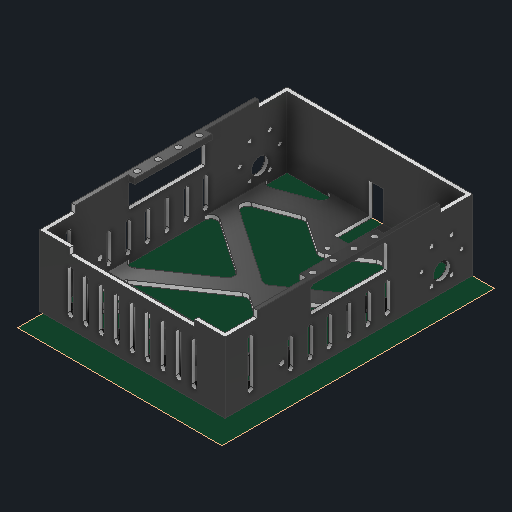
# Autodesk Inventor part: 01_4_2_support_electronique_moteur_v2
Saved by Autodesk Inventor 2026 (Build 300175000, 175)
## iProperties
Created: 2025-06-04
Part Number: 01_4_2_support_electronique_moteur_v2
Material: Générique
Document SubType Name: Modeling
Designer: virgi
Density: 1 g/cm^3
Appearance: Par défaut
Author: virgi
Autodesk Inventor part; units mm, degrees
ref_plane "YZ Plane" through (0, 0, 0) normal (1, 0, 0) x (0, 1, 0)
ref_plane "XZ Plane" through (0, 0, 0) normal (0, 1, 0) x (-1, 0, 0)
ref_plane "XY Plane" through (0, 0, 0) normal (0, 0, 1) x (1, 0, 0)
sketch "Esquisse1" plane through (0, 0, 0) normal (0, 1, 0) x (-1, 0, 0)
  line L0 (-72, -96) -> (72, -96)
  line L1 (72, -96) -> (72, 96)
  line L2 (72, 96) -> (-72, 96)
  line L3 (-72, 96) -> (-72, -96)
  line L4 (-72, -96) -> (72, 96) construction
  line L5 (72, -96) -> (-72, 96) construction
  point P0 (0, 0)
  dimension "d0" = 192
  dimension "d1" = 144
  constraints: 12 end point, 2 midpoint, 2 parallel, 1 horizontal, 1 perpendicular
  measures "d0" distance of L0.end L1.end
  measures "d1" distance of L0.start L0.end
extrude "bloc initial" add sketch "Esquisse1" along normal blind 60
sketch "Esquisse2" plane through (0, 60, 0) normal (0, 1, 0) x (1, 0, 0)
  line L0 (69, 93) -> (-69, 93)
  line L1 (-69, 93) -> (-69, -93)
  line L2 (-69, -93) -> (69, -93)
  line L3 (69, -93) -> (69, 93)
  line L4 (69, 93) -> (-69, -93) construction
  line L5 (-69, 93) -> (69, -93) construction
  line L6 (-72, -96) -> (72, -96) projected
  line L7 (-72, 96) -> (-72, -96) projected
  point P0 (0, 0)
  dimension "d4" = 3
  dimension "d5" = 3
  constraints: 12 end point, 2 midpoint, 2 parallel, 1 horizontal, 1 perpendicular
  measures "d4" distance between parallel lines of L6 L2
  measures "d5" distance between parallel lines of L7 L1
extrude "volume interieur" cut sketch "Esquisse2" against normal blind 57
sketch "Esquisse3" plane through (0, 60, 0) normal (0, 1, 0) x (1, 0, 0)
  line L0 (-69, 30) -> (-64, 30)
  line L1 (-64, 30) -> (-64, -30)
  line L2 (-64, -30) -> (-69, -30)
  line L3 (-69, -30) -> (-69, 30)
  line L4 (-69, 30) -> (-64, -30) construction
  line L5 (-64, 30) -> (-69, -30) construction
  line L6 (-69, -93) -> (-69, 93) projected
  line L7 (-72, 96) -> (-72, -96) projected
  point P0 (0, 0)
  point P1 (-66.5, 0)
  point P2 (-72, -30)
  point P3 (-72, 30)
  dimension "d13" = 60
  dimension "d14" = 0
  dimension "d148" = 5
  constraints: 12 end point, 2 midpoint, 2 parallel, 1 collinear, 1 horizontal, 1 perpendicular
  measures "d13" distance between parallel lines of L0 L2
  measures "d14" vertical distance of point (0, 0) point (-66.5, 0)
  measures "d148" distance between parallel lines of L6 L1
extrude "vorsprung de maintient" add sketch "Esquisse3" against normal blind 4
sketch "Esquisse4" plane through (0, 60, 0) normal (0, 1, 0) x (1, 0, 0)
  line L0 (-64, -30) -> (-64, 30) projected
  line L1 (-69, 30) -> (-69, 93) projected
  line L2 (-72, 96) -> (-72, -96) projected
  point P0 (0, 0)
  point P1 (-72, 30)
  point P2 (-68, 24)
  point P3 (-105.6247, 24)
  dimension "d153" = 4
  constraints: 1 horizontal alignment, 2 other
  measures "d153" distance from line of L2 point (-68, 24)
hole "8*trous attache chassis" at (-68, 60, -24) direction (0, -1, 0) diameter 4.5 depth 20 tip angle 118
pattern_linear "Réseau rectangulaire1" count 4 spacing 16 along (0, 0, 1) of "8*trous attache chassis"
mirror "Mise en miroir2" about plane through (0, 0, 0) normal (1, 0, 0) of "vorsprung de maintient", "8*trous attache chassis", "Réseau rectangulaire1"
sketch "Esquisse5" plane through (0, 60, 0) normal (0, 1, 0) x (1, 0, 0)
  line L0 (-72, 71) -> (72, 71)
  line L1 (72, 71) -> (72, 96)
  line L2 (72, 96) -> (-72, 96)
  line L3 (-72, 96) -> (-72, 71)
  line L4 (-72, 71) -> (72, 96) construction
  line L5 (72, 71) -> (-72, 96) construction
  point P0 (0, 0)
  point P1 (0, 83.5)
  dimension "d29" = 71
  dimension "d32" = 0
  constraints: 12 end point, 2 coincident, 2 midpoint, 2 parallel, 1 horizontal, 1 perpendicular
  measures "d29" distance from line of point (0, 0) L0
  measures "d32" horizontal distance of point (0, 0) point (0, 83.5)
extrude "encoches chassis" cut sketch "Esquisse5" against normal blind 5.5
mirror "Mise en miroir encoches" about plane through (0, 0, 0) normal (0, 0, 1) of "encoches chassis"
sketch "Esquisse7" plane through (-72, 0, -96) normal (-1, 0, 0) x (0, 0, 1)
  line L0 (192, 0) -> (192, 60) projected
  line L1 (0, 0) -> (192, 0) projected
  line L2 (25, 60) -> (192, 60) projected
  point P0 (96, 0)
  point P1 (148, 15)
  point P2 (192, 54.5)
  point P3 (126, 60)
  point P4 (167, 60)
  dimension "d47" = 44
  dimension "d49" = 45
  measures "d47" distance from line of L0 point (148, 15)
  measures "d49" distance from line of L2 point (148, 15)
hole "axe roues arrieres" at (-72, 15, 52) direction (1, 0, 0) diameter 4.5 end through all
sketch "Esquisse8" plane through (-72, 0, -96) normal (-1, 0, 0) x (0, 0, 1)
  line L0 (0, 60) -> (192, 60) projected
  line L1 (0, 0) -> (0, 60) projected
  line L2 (0, 0) -> (192, 0) projected
  point P0 (96, 0)
  point P1 (24, 15)
  point P2 (25, 60)
  point P3 (66, 60)
  point P4 (0, 54.5)
  point P5 (96, 0)
  dimension "d57" = 45
  dimension "d60" = 72
  constraints: 1 midpoint
  measures "d57" distance from line of point (24, 15) L0
  measures "d60" horizontal distance of point (24, 15) point (96, 0)
hole "axes moteur" at (-72, 15, -72) direction (1, 0, 0) diameter 13.2 end through all
sketch "Esquisse9" plane through (-72, 0, -96) normal (-1, 0, 0) x (0, 0, 1)
  circle A0 centre (24, 22) radius 15.5 construction
  circle A1 centre (24, 15) radius 6.6 construction
  point P0 (96, 0)
  point P1 (39.5, 22)
  point P2 (31.75, 35.4234)
  point P3 (16.25, 35.4234)
  point P4 (8.5, 22)
  point P5 (16.25, 8.5766)
  point P6 (31.75, 8.5766)
  dimension "d70" = 31
  dimension "d68" = 7
  dimension "d69" = 0
  dimension "d71" = 0
  dimension "d74" = 360
  constraints: 2 coincident, 1 horizontal alignment, 13 other
  measures "d68" distance of A1.centre point (24, 22)
  measures "d69" horizontal distance of A1.centre point (24, 22)
  measures "d71" vertical distance of point (24, 22) point (39.5, 22)
hole "trous moteur" at (-72, 22, -56.5) at (-72, 35.4234, -64.25) at (-72, 35.4234, -79.75) at (-72, 22, -87.5) at (-72, 8.5766, -79.75) at (-72, 8.5766, -64.25) direction (1, 0, 0) diameter 3.5 end through all
sketch "Esquisse12" plane through (0, 60, 0) normal (0, 1, 0) x (1, 0, 0)
  line L0 (-48.25, -96) -> (48.25, -96)
  line L1 (48.25, -96) -> (48.25, -93)
  line L2 (48.25, -93) -> (-48.25, -93)
  line L3 (-48.25, -93) -> (-48.25, -96)
  line L4 (-48.25, -96) -> (48.25, -93) construction
  line L5 (48.25, -96) -> (-48.25, -93) construction
  line L6 (72, -96) -> (-72, -96) projected
  line L7 (-69, -93) -> (69, -93) projected
  point P0 (0, 0)
  point P1 (0, -94.5)
  point P2 (65, -96)
  point P3 (-65, -96)
  point P4 (-65, -92)
  point P5 (65, -92)
  dimension "d106" = 96.5
  dimension "d109" = 0
  constraints: 12 end point, 2 horizontal, 2 midpoint, 2 parallel, 1 collinear, 1 perpendicular, 1 other
  measures "d106" distance between parallel lines of L3 L1
  measures "d109" horizontal distance of point (0, 0) point (0, -94.5)
extrude "encoche chassis arriere" cut sketch "Esquisse12" against normal blind 10.5
sketch "Esquisse13" plane through (0, 3, 0) normal (0, 1, 0) x (1, 0, 0)
  line L0 (0, 5.631) -> (-69, 53)
  line L1 (69, 53) -> (0, 5.631)
  line L2 (0, -116.7872) -> (0, 160.5594) construction
  line L3 (-69, -93) -> (-69, 93) projected
  line L4 (-77.1225, 0) -> (59.0886, 0) construction
  line L5 (-74.2887, 0) -> (57.0105, 0) construction
  line L6 (0, -5.631) -> (-69, -53)
  line L7 (-69, -53) -> (69, -53)
  line L8 (69, -53) -> (0, -5.631)
  line L9 (-13, 0) -> (-69, -38.4444)
  line L10 (-69, -38.4444) -> (-69, 38.4444)
  line L11 (-13, 0) -> (-69, 38.4444)
  line L12 (-69, -38.4444) -> (-69, 38.4444)
  line L13 (13, 0) -> (69, -38.4444)
  line L14 (69, -38.4444) -> (69, 38.4444)
  line L15 (13, 0) -> (69, 38.4444)
  line L16 (-69, 53) -> (-29, 67.8231)
  line L17 (9.4839, 93) -> (69, 70.9446)
  line L18 (69, 70.9446) -> (69, 93)
  line L19 (69, 93) -> (9.4839, 93)
  line L20 (69, 93) -> (69, -93) projected
  line L21 (69, 93) -> (-69, 93) projected
  line L22 (-9.4839, 93) -> (-69, 70.9446)
  line L23 (-69, 70.9446) -> (-69, 93)
  line L24 (-69, 93) -> (-9.4839, 93)
  line L25 (-48.25, -93) -> (48.25, -93) projected
  line L26 (-72, 96) -> (72, 96) projected
  line L27 (8.125, 96) -> (8.125, 65.9) construction
  line L28 (8.125, 96) -> (38.225, 96) construction
  line L29 (8.125, 65.9) -> (0, 65.9) construction
  line L30 (8.125, 96) -> (0, 96) construction
  line L31 (-8.125, 96) -> (-8.125, 65.9) construction
  line L32 (-8.125, 65.9) -> (0, 65.9) construction
  line L33 (-8.125, 96) -> (0, 96) construction
  circle A0 centre (-1.5, 54.9) radius 2 construction
  line L34 (-29, 67.8231) -> (0, 48.2272)
  line L35 (29, 67.8231) -> (0, 48.2272)
  line L36 (29, 67.8231) -> (69, 53)
  point P0 (0, 0)
  point P1 (-69, -71)
  point P2 (-69, 71)
  point P3 (0, 83.6463)
  point P4 (69, 71)
  point P5 (69, -71)
  point P6 (-69, 70.9446)
  point P7 (-69, 70.9446)
  point P8 (65, 92)
  point P9 (-65, 92)
  point P10 (-65, 96)
  point P11 (65, 96)
  dimension "d114" = 12
  dimension "d126" = 40
  dimension "d136" = 30.1
  dimension "d137" = 90
  dimension "d138" = 8.125
  dimension "d139" = 4
  dimension "d142" = 11
  dimension "d143" = 9.625
  dimension "d144" = 35
  dimension "d161" = 56
  constraints: 60 end point, 13 point on line, 13 symmetric about line, 4 vertical, 3 parallel, 2 horizontal, 2 perpendicular, 1 centre point, 1 collinear, 1 midpoint, 10 other
  measures "d114" distance from line of L11 L0.start
  measures "d126" distance between parallel lines of L25 L7
  measures "d136" distance of L27.start L27.end
  measures "d137" angle of L27 L28
  measures "d138" distance of L27.end L29.end
  measures "d139" diameter of A0
  measures "d142" distance from line of L29 A0.centre
  measures "d143" distance from line of L27 A0.centre
  measures "d144" distance of L16.end L34.end
  measures "d161" distance from line of L3 L9.start
extrude "structure bas" cut sketch "Esquisse13" against normal blind 10 contours L0 L16 L34 L35 L36 L1 | L11 L9 L3 | L3 L21 L22 | L17 L19 L18 | L14 L13 L15 | L6 L8 L7
sketch "Esquisse14" plane through (0, 3, 0) normal (0, 1, 0) x (1, 0, 0)
  line L0 (-69, -56) -> (69, -56)
  line L1 (69, -56) -> (69, -58)
  line L2 (69, -58) -> (-69, -58)
  line L3 (-69, -58) -> (-69, -56)
  line L4 (-48.25, -93) -> (48.25, -93) projected
  line L5 (-69, -93) -> (-69, -53) projected
  line L6 (69, -53) -> (69, -93) projected
  point P0 (0, 0)
  point P1 (-69, -57)
  point P2 (69, -57)
  dimension "d117" = 35
  dimension "d118" = 2
  constraints: 8 end point, 3 point on line, 2 midpoint, 2 parallel, 1 horizontal, 1 perpendicular
  measures "d117" distance between parallel lines of L4 L2
  measures "d118" distance between parallel lines of L2 L0
extrude "Extrusion8" add sketch "Esquisse14" along normal blind 10
chamfer "Chanfrein3" distance 2 angle 45 1 edges at (0, 3, 56)
fillet "Congé1" radius 5 19 edges at (69, 1.5, -53) (0, 1.5, -5.631) (0, 1.5, 5.631) (69, 1.5, 53) (69, 1.5, 38.4444) (69, 1.5, -38.4444) (-13, 1.5, 0) (-69, 1.5, -38.4444) (-69, 1.5, -53) (-9.4839, 1.5, -93) (9.4839, 1.5, -93) (69, 1.5, -70.9446) (-69, 1.5, 38.4444) (-69, 1.5, 53) (13, 1.5, 0) (29, 1.5, -67.8231) (-29, 1.5, -67.8231) (0, 1.5, -48.2272) (-69, 1.5, -70.9446)
sketch "Esquisse15" plane through (0, 0, 0) normal (0, -1, 0) x (1, 0, 0)
  line L0 (72, -96) -> (-72, -96) projected
  line L1 (5.625, -96) -> (5.625, -65.9)
  line L2 (5.625, -96) -> (35.725, -96) construction
  line L3 (5.625, -65.9) -> (0, -65.9)
  line L4 (0, -162.9029) -> (0, 159.6719) construction
  line L5 (5.625, -96) -> (0, -96)
  line L6 (-5.625, -96) -> (-5.625, -65.9)
  line L7 (-5.625, -65.9) -> (0, -65.9)
  line L8 (-5.625, -96) -> (0, -96)
  circle A0 centre (0.5, -54.9) radius 2
  point P0 (0, 0)
  point P1 (-5.625, -96)
  dimension "d129" = 30.1
  dimension "d130" = 90
  dimension "d131" = 5.625
  dimension "d132" = 4
  dimension "d133" = 11
  dimension "d145" = 5.125
  constraints: 16 end point, 3 point on line, 3 vertical, 2 perpendicular, 2 symmetric about line, 1 centre point, 1 horizontal, 1 midpoint
  measures "d129" distance of L1.start L1.end
  measures "d130" angle of L2 L1
  measures "d131" distance of L1.end L3.end
  measures "d132" diameter of A0
  measures "d133" distance from line of L7 A0.centre
  measures "d145" distance from line of L1 A0.centre
extrude "Extrusion9" cut sketch "Esquisse15" against normal blind 26.5
sketch "Esquisse17" plane through (-72, 0, -96) normal (-1, 0, 0) x (0, 0, 1)
  line L0 (66, 56) -> (126, 56)
  line L1 (126, 56) -> (126, 36)
  line L2 (126, 36) -> (66, 36)
  line L3 (66, 36) -> (66, 56)
  line L4 (96, -10.3773) -> (96, 75.4229) construction
  line L5 (25, 60) -> (167, 60) projected
  line L6 (0, 0) -> (192, 0) projected
  point P0 (96, 0)
  point P1 (126, 60)
  point P2 (96, 0)
  dimension "d154" = 4
  dimension "d155" = 20
  constraints: 10 end point, 2 parallel, 2 point on line, 1 horizontal, 1 midpoint, 1 perpendicular, 1 symmetric about line, 1 vertical
  measures "d154" distance between parallel lines of L0 L5
  measures "d155" distance between parallel lines of L0 L2
extrude "Extrusion10" cut sketch "Esquisse17" against normal through all
chamfer "Chanfrein4" distance 2 angle 45 4 edges at (-70.5, 56, -30) (-70.5, 56, 30) (70.5, 56, -30) (70.5, 56, 30)
sketch "Esquisse18" plane through (0, 3, 0) normal (0, 1, 0) x (1, 0, 0)
  line L0 (64.1901, -58) -> (36.2612, -58)
  line L1 (64.1901, -93) -> (36.2612, -93)
  line L2 (69, -93) -> (69, -71) construction
  line L3 (-48.25, -93) -> (48.25, -93) construction
  line L4 (-69, -58) -> (69, -58) construction
  line L5 (69, -75.5) -> (-10.9961, -75.5) construction
  line L6 (69, -58) -> (69, -93) construction
  line L7 (0, -58) -> (35, -93) construction
  line L8 (0, -58) -> (49.4975, -58) construction
  line L9 (0, -93) -> (35, -58) construction
  line L10 (0, -93) -> (49.4975, -93) construction
  line L11 (-16.551, -45.6916) -> (50.7712, -113.0138) construction
  line L12 (4.2426, -58) -> (57.1295, -110.8869) construction
  line L13 (0.5831, -88.1743) -> (45.6918, -43.0655) construction
  line L14 (4.2426, -93) -> (48.9144, -48.3283) construction
  line L15 (4.2426, -58) -> (17.5, -71.2574)
  line L16 (17.5, -71.2574) -> (30.7574, -58)
  line L17 (0, -62.2426) -> (13.2574, -75.5)
  line L18 (13.2574, -75.5) -> (0, -88.7574)
  line L19 (4.2426, -93) -> (17.5, -79.7426)
  line L20 (17.5, -79.7426) -> (30.7574, -93)
  line L21 (0, 0) -> (0, -187.8639) construction
  line L22 (21.7426, -75.5) -> (35, -62.2426)
  line L23 (21.7426, -75.5) -> (35, -88.7574)
  line L24 (0, 0) -> (0, -136.1156) construction
  line L25 (0, -58) -> (-35, -93) construction
  line L26 (0, -93) -> (-35, -58) construction
  line L27 (-4.2426, -58) -> (-17.5, -71.2574)
  line L28 (-17.5, -71.2574) -> (-30.7574, -58)
  line L29 (0, -62.2426) -> (-13.2574, -75.5)
  line L30 (-13.2574, -75.5) -> (0, -88.7574)
  line L31 (-4.2426, -93) -> (-17.5, -79.7426)
  line L32 (-17.5, -79.7426) -> (-30.7574, -93)
  line L33 (-21.7426, -75.5) -> (-35, -62.2426)
  line L34 (-21.7426, -75.5) -> (-35, -88.7574)
  line L35 (-35, -44.006) -> (-35, -148.5262) construction
  line L36 (-52.5, -79.7426) -> (-39.2426, -93)
  line L37 (-70, -62.2426) -> (-56.7426, -75.5)
  line L38 (-65.7574, -93) -> (-52.5, -79.7426)
  line L39 (-70, -58) -> (-35, -93) construction
  line L40 (-48.2574, -75.5) -> (-35, -62.2426)
  line L41 (-48.2574, -75.5) -> (-35, -88.7574)
  line L42 (-56.7426, -75.5) -> (-70, -88.7574)
  line L43 (-65.7574, -58) -> (-52.5, -71.2574)
  line L44 (-70, -93) -> (-35, -58) construction
  line L45 (-52.5, -71.2574) -> (-39.2426, -58)
  line L46 (35, -42.0368) -> (35, -145.5) construction
  line L47 (70, -58) -> (35, -93) construction
  line L48 (70, -93) -> (35, -58) construction
  line L49 (65.7574, -58) -> (52.5, -71.2574)
  line L50 (52.5, -71.2574) -> (39.2426, -58)
  line L51 (70, -62.2426) -> (56.7426, -75.5)
  line L52 (56.7426, -75.5) -> (70, -88.7574)
  line L53 (65.7574, -93) -> (52.5, -79.7426)
  line L54 (52.5, -79.7426) -> (39.2426, -93)
  line L55 (48.2574, -75.5) -> (35, -62.2426)
  line L56 (48.2574, -75.5) -> (35, -88.7574)
  line L57 (69, -63.2426) -> (69, -87.7574)
  line L58 (65.7574, -58) -> (39.2426, -58)
  line L59 (65.7574, -93) -> (39.2426, -93)
  line L60 (30.7574, -93) -> (4.2426, -93)
  line L61 (30.7574, -58) -> (4.2426, -58)
  line L62 (-4.2426, -58) -> (-30.7574, -58)
  line L63 (-30.7574, -93) -> (-4.2426, -93)
  line L64 (-39.2426, -93) -> (-65.7574, -93)
  line L65 (-39.2426, -58) -> (-65.7574, -58)
  line L66 (-69, -63.2426) -> (-69, -87.7574)
  point P0 (65, -75.5)
  point P1 (-36.2612, -58)
  point P2 (-36.2612, -93)
  point P3 (-0.5831, -88.1743)
  point P4 (-59.0039, -75.5)
  point P5 (-53.449, -45.6916)
  point P6 (-70.5831, -88.1743)
  point P7 (-70, -62.2426)
  point P8 (-33.7388, -93)
  point P9 (-33.7388, -58)
  point P10 (-69.4169, -88.1743)
  point P11 (33.7388, -58)
  point P12 (33.7388, -93)
  point P13 (69.4169, -88.1743)
  point P14 (70, -62.2426)
  point P15 (70.5831, -88.1743)
  dimension "d167" = 45
  dimension "d168" = 45
  dimension "d171" = 3
  dimension "d172" = 3
  dimension "d175" = 3
  dimension "d176" = 3
  dimension "d177" = 18.7487
  constraints: 126 end point, 57 symmetric about line, 31 point on line, 6 collinear, 3 horizontal, 3 midpoint, 3 parallel, 3 vertical, 2 equal length, 2 perpendicular
  measures "d167" angle of L7 L8
  measures "d168" angle of L10 L9
  measures "d171" distance between parallel lines of L7 L11
  measures "d172" distance between parallel lines of L7 L12
  measures "d175" distance between parallel lines of L9 L13
  measures "d176" distance between parallel lines of L9 L14
  measures "d177" distance of L17.start L17.end
extrude "Extrusion11" cut sketch "Esquisse18" against normal through all
fillet "Congé2" radius 2 38 edges at (-69, 1.5, 63.2426) (-65.7574, 1.5, 58) (-39.2426, 1.5, 58) (-52.5, 1.5, 71.2574) (-56.7426, 1.5, 75.5) (-69, 1.5, 87.7574) (-65.7574, 1.5, 93) (-52.5, 1.5, 79.7426) (-39.2426, 1.5, 93) (-48.2574, 1.5, 75.5) (-35, 1.5, 62.2426) (-35, 1.5, 88.7574) (-21.7426, 1.5, 75.5) (-17.5, 1.5, 71.2574) (-30.7574, 1.5, 58) (-4.2426, 1.5, 58) (-17.5, 1.5, 79.7426) (-30.7574, 1.5, 93) (-4.2426, 1.5, 93) (30.7574, 1.5, 93) (13.2574, 1.5, 75.5) (0, 1.5, 88.7574) (4.2426, 1.5, 93) (-13.2574, 1.5, 75.5) (17.5, 1.5, 79.7426) (0, 1.5, 62.2426) (4.2426, 1.5, 58) (21.7426, 1.5, 75.5) (17.5, 1.5, 71.2574) (35, 1.5, 88.7574) (30.7574, 1.5, 58) (48.2574, 1.5, 75.5) (65.7574, 1.5, 58) (35, 1.5, 62.2426) (39.2426, 1.5, 58) (52.5, 1.5, 71.2574) (52.5, 1.5, 79.7426) (65.7574, 1.5, 93)
fillet "Congé3" radius 2 4 edges at (69, 1.5, 63.2426) (69, 1.5, 87.7574) (56.7426, 1.5, 75.5) (39.2426, 1.5, 93)
sketch "Esquisse21" plane through (-72, 0, -96) normal (-1, 0, 0) x (0, 0, 1)
  line L0 (126, 36) -> (66, 36) construction
  line L1 (0, 0) -> (192, 0) construction
  line L2 (96, 28) -> (96, 8) construction
  line L3 (93.8, 28) -> (93.8, 8)
  line L4 (98.2, 8) -> (98.2, 28)
  arc A0 (98.2, 28) -> (93.8, 28) centre (96, 28) ccw
  arc A1 (93.8, 8) -> (98.2, 8) centre (96, 8) ccw
  line L5 (96, 36) -> (96, 0) construction
  line L6 (81, 28) -> (81, 8) construction
  line L7 (78.8, 28) -> (78.8, 8)
  line L8 (83.2, 8) -> (83.2, 28)
  arc A2 (83.2, 28) -> (78.8, 28) centre (81, 28) ccw
  arc A3 (78.8, 8) -> (83.2, 8) centre (81, 8) ccw
  line L9 (66, 28) -> (66, 8) construction
  line L10 (63.8, 28) -> (63.8, 8)
  line L11 (68.2, 8) -> (68.2, 28)
  arc A4 (68.2, 28) -> (63.8, 28) centre (66, 28) ccw
  arc A5 (63.8, 8) -> (68.2, 8) centre (66, 8) ccw
  line L12 (111, 28) -> (111, 8) construction
  line L13 (108.8, 28) -> (108.8, 8)
  arc A6 (113.2, 28) -> (108.8, 28) centre (111, 28) ccw
  line L14 (111, 36) -> (111, 0) construction
  arc A7 (108.8, 8) -> (113.2, 8) centre (111, 8) ccw
  line L15 (113.2, 8) -> (113.2, 28)
  line L16 (126, 28) -> (126, 8) construction
  line L17 (123.8, 28) -> (123.8, 8)
  arc A8 (128.2, 28) -> (123.8, 28) centre (126, 28) ccw
  line L18 (126, 36) -> (126, 0) construction
  arc A9 (123.8, 8) -> (128.2, 8) centre (126, 8) ccw
  line L19 (128.2, 8) -> (128.2, 28)
  line L20 (141, 28) -> (141, 8) construction
  line L21 (138.8, 28) -> (138.8, 8)
  arc A10 (143.2, 28) -> (138.8, 28) centre (141, 28) ccw
  line L22 (141, 36) -> (141, 0) construction
  arc A11 (138.8, 8) -> (143.2, 8) centre (141, 8) ccw
  line L23 (143.2, 8) -> (143.2, 28)
  line L24 (172.1622, 44.4439) -> (172.1622, 9.4439) construction
  line L25 (169.9622, 44.4439) -> (169.9622, 9.4439)
  line L26 (174.3622, 9.4439) -> (174.3622, 44.4439)
  arc A12 (174.3622, 44.4439) -> (169.9622, 44.4439) centre (172.1622, 44.4439) ccw
  arc A13 (169.9622, 9.4439) -> (174.3622, 9.4439) centre (172.1622, 9.4439) ccw
  point P0 (96, 18)
  point P1 (96, 18)
  point P2 (81, 18)
  point P3 (81, 18)
  point P4 (66, 18)
  point P5 (66, 18)
  point P6 (111, 18)
  point P7 (111, 18)
  point P8 (126, 18)
  point P9 (126, 18)
  point P10 (141, 18)
  point P11 (141, 18)
  point P12 (172.1622, 26.9439)
  dimension "d196" = 20
  dimension "d197" = 4.4
  dimension "d200" = 15
  dimension "d207" = 15
  dimension "d232" = 35
  dimension "d233" = 4.4
  constraints: 64 end point, 28 point on circle, 14 centre point, 8 tangent, 6 coincident, 5 midpoint, 2 horizontal, 2 parallel, 1 collinear, 1 vertical, 74 other
  measures "d196" distance of L2.start L2.end
  measures "d197" diameter of A1
  measures "d200" distance of L3.start L7.start
  measures "d207" distance of L3.start L13.start
  measures "d232" distance of L24.start L24.end
  measures "d233" diameter of A13
extrude "Extrusion13" cut sketch "Esquisse21" against normal through all
sketch "Esquisse22" plane through (-72, 0, 96) normal (0, 0, 1) x (1, 0, 0)
  line L0 (72, 49.6187) -> (72, 0) construction
  line L1 (72, 39.6393) -> (72, 9.6393) construction
  line L2 (69.8, 39.6393) -> (69.8, 9.6393)
  line L3 (74.2, 9.6393) -> (74.2, 39.6393)
  arc A0 (74.2, 39.6393) -> (69.8, 39.6393) centre (72, 39.6393) ccw
  arc A1 (69.8, 9.6393) -> (74.2, 9.6393) centre (72, 9.6393) ccw
  line L4 (28.7867, 49.6187) -> (110.5175, 49.6187) construction
  line L5 (84, 39.6393) -> (84, 9.6393) construction
  line L6 (81.8, 39.6393) -> (81.8, 9.6393)
  line L7 (86.2, 9.6393) -> (86.2, 39.6393)
  arc A2 (86.2, 39.6393) -> (81.8, 39.6393) centre (84, 39.6393) ccw
  arc A3 (81.8, 9.6393) -> (86.2, 9.6393) centre (84, 9.6393) ccw
  line L8 (96, 39.6393) -> (96, 9.6393) construction
  line L9 (93.8, 39.6393) -> (93.8, 9.6393)
  line L10 (98.2, 9.6393) -> (98.2, 39.6393)
  arc A4 (98.2, 39.6393) -> (93.8, 39.6393) centre (96, 39.6393) ccw
  arc A5 (93.8, 9.6393) -> (98.2, 9.6393) centre (96, 9.6393) ccw
  line L11 (108, 39.6393) -> (108, 9.6393) construction
  line L12 (105.8, 39.6393) -> (105.8, 9.6393)
  line L13 (110.2, 9.6393) -> (110.2, 39.6393)
  arc A6 (110.2, 39.6393) -> (105.8, 39.6393) centre (108, 39.6393) ccw
  arc A7 (105.8, 9.6393) -> (110.2, 9.6393) centre (108, 9.6393) ccw
  arc A8 (57.8, 9.6393) -> (62.2, 9.6393) centre (60, 9.6393) ccw
  line L14 (57.8, 39.6393) -> (57.8, 9.6393)
  line L15 (60, 39.6393) -> (60, 9.6393) construction
  line L16 (62.2, 9.6393) -> (62.2, 39.6393)
  arc A9 (62.2, 39.6393) -> (57.8, 39.6393) centre (60, 39.6393) ccw
  arc A10 (45.8, 9.6393) -> (50.2, 9.6393) centre (48, 9.6393) ccw
  line L17 (45.8, 39.6393) -> (45.8, 9.6393)
  line L18 (48, 39.6393) -> (48, 9.6393) construction
  line L19 (50.2, 9.6393) -> (50.2, 39.6393)
  arc A11 (50.2, 39.6393) -> (45.8, 39.6393) centre (48, 39.6393) ccw
  arc A12 (33.8, 9.6393) -> (38.2, 9.6393) centre (36, 9.6393) ccw
  line L20 (33.8, 39.6393) -> (33.8, 9.6393)
  line L21 (36, 39.6393) -> (36, 9.6393) construction
  line L22 (38.2, 9.6393) -> (38.2, 39.6393)
  arc A13 (38.2, 39.6393) -> (33.8, 39.6393) centre (36, 39.6393) ccw
  line L23 (120, 39.6393) -> (120, 9.6393) construction
  line L24 (117.8, 39.6393) -> (117.8, 9.6393)
  line L25 (122.2, 9.6393) -> (122.2, 39.6393)
  arc A14 (122.2, 39.6393) -> (117.8, 39.6393) centre (120, 39.6393) ccw
  arc A15 (117.8, 9.6393) -> (122.2, 9.6393) centre (120, 9.6393) ccw
  arc A16 (21.8, 9.6393) -> (26.2, 9.6393) centre (24, 9.6393) ccw
  line L26 (21.8, 39.6393) -> (21.8, 9.6393)
  line L27 (24, 39.6393) -> (24, 9.6393) construction
  line L28 (26.2, 9.6393) -> (26.2, 39.6393)
  arc A17 (26.2, 39.6393) -> (21.8, 39.6393) centre (24, 39.6393) ccw
  point P0 (72, 24.6393)
  point P1 (84, 24.6393)
  point P2 (96, 24.6393)
  point P3 (108, 24.6393)
  point P4 (60, 24.6393)
  point P5 (48, 24.6393)
  point P6 (36, 24.6393)
  point P7 (120, 24.6393)
  point P8 (24, 24.6393)
  dimension "d214" = 30
  dimension "d215" = 4.4
  dimension "d218" = 12
  dimension "d225" = 12
  constraints: 76 end point, 36 point on circle, 18 centre point, 4 tangent, 3 horizontal, 2 point on line, 1 midpoint, 1 parallel, 1 vertical, 96 other
  measures "d214" distance of L1.start L1.end
  measures "d215" diameter of A1
  measures "d218" distance of L2.start L6.start
  measures "d225" distance of L2.end L14.end
extrude "Extrusion14" cut sketch "Esquisse22" against normal blind 3
ref_plane "Plan de construction1" through (0, -10, 0) normal (0, -1, 0) x (1, 0, 0)
